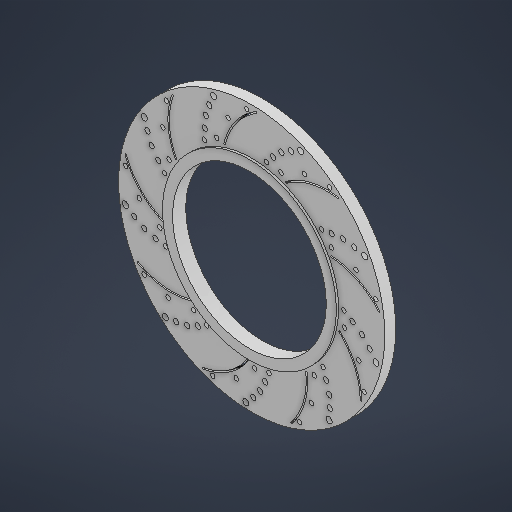
# Autodesk Inventor part: disc2 front face
Saved by Autodesk Inventor 2027 (Build 310192060, 192F)
## iProperties
Created: 2026-07-10
Part Number: disc2 front face
Material: Generic
Document SubType Name: Modeling
Designer: ElieH
Density: 1 g/cm^3
Appearance: Default
Author: ElieH
Autodesk Inventor part; units mm, degrees
ref_plane "YZ Plane" through (0, 0, 0) normal (1, 0, 0) x (0, 1, 0)
ref_plane "XZ Plane" through (0, 0, 0) normal (0, 1, 0) x (-1, 0, 0)
ref_plane "XY Plane" through (0, 0, 0) normal (0, 0, 1) x (1, 0, 0)
sketch "Sketch1" plane through (0, 0, 0) normal (0, 0, 1) x (1, 0, 0)
  arc A0 (-102.94, 86.9125) -> (-99.2877, 29.5739) centre (-33.093, 62.5759) ccw
  arc A1 (-99.5994, 28.6316) -> (-99.2877, 29.5739) centre (-99.9181, 29.2597) ccw
  line L0 (-99.5994, 28.6316) -> (-99.7654, 28.5473)
  arc A2 (-100.7145, 28.8611) -> (-99.7654, 28.5473) centre (-100.0841, 29.1754) ccw
  arc A3 (-104.4457, 87.4385) -> (-100.7145, 28.8611) centre (-33.093, 62.5759) ccw
  arc A4 (-103.5441, 87.8703) -> (-104.4457, 87.4385) centre (-103.7805, 87.2068) ccw
  line L1 (-103.5441, 87.8703) -> (-103.3687, 87.8077)
  arc A5 (-102.94, 86.9125) -> (-103.3687, 87.8077) centre (-103.6051, 87.1443) ccw
  arc A6 (-140.9056, -88.565) -> (-83.804, -94.925) centre (-104.8099, -24.0052) ccw
  arc A7 (-82.93, -95.3955) -> (-83.804, -94.925) centre (-83.6039, -95.6003) ccw
  line L2 (-82.93, -95.3955) -> (-82.8759, -95.5737)
  arc A8 (-83.3497, -96.4538) -> (-82.8759, -95.5737) centre (-83.5498, -95.7785) ccw
  arc A9 (-141.6851, -89.9565) -> (-83.3497, -96.4538) centre (-104.8099, -24.0052) ccw
  arc A10 (-141.9537, -88.9936) -> (-141.6851, -89.9565) centre (-141.3414, -89.3417) ccw
  line L3 (-141.9537, -88.9936) -> (-141.8617, -88.8317)
  arc A11 (-140.9056, -88.565) -> (-141.8617, -88.8317) centre (-141.2494, -89.1798) ccw
  arc A12 (25.3133, -156.4252) -> (41.4923, -101.2954) centre (-31.9977, -109.6672) ccw
  arc A13 (42.1074, -100.5165) -> (41.4923, -101.2954) centre (42.1921, -101.2157) ccw
  line L4 (42.1074, -100.5165) -> (42.2923, -100.4941)
  arc A14 (43.0768, -101.1136) -> (42.2923, -100.4941) centre (42.377, -101.1933) ccw
  arc A15 (26.5483, -157.4345) -> (43.0768, -101.1136) centre (-31.9977, -109.6672) ccw
  arc A16 (25.5534, -157.5318) -> (26.5483, -157.4345) centre (26.0025, -156.9892) ccw
  line L5 (25.5534, -157.5318) -> (25.41, -157.4131)
  arc A17 (25.3133, -156.4252) -> (25.41, -157.4131) centre (25.8591, -156.8705) ccw
  arc A18 (121.0062, -4.5153) -> (69.5234, 20.9911) centre (65.0066, -52.8362) ccw
  arc A19 (68.8631, 21.7321) -> (69.5234, 20.9911) centre (69.5664, 21.6941) ccw
  line L6 (68.8631, 21.7321) -> (68.8732, 21.9181)
  arc A20 (69.6195, 22.5831) -> (68.8732, 21.9181) centre (69.5765, 21.88) ccw
  arc A21 (122.2146, -3.4744) -> (69.6195, 22.5831) centre (65.0066, -52.8362) ccw
  arc A22 (122.1377, -4.471) -> (122.2146, -3.4744) centre (121.6813, -3.9345) ccw
  line L7 (122.1377, -4.471) -> (121.9958, -4.5917)
  arc A23 (121.0062, -4.5153) -> (121.9958, -4.5917) centre (121.5395, -4.0551) ccw
  arc A24 (76.4643, 79.995) -> (20.631, 66.4415) centre (64.6262, 6.9832) ccw
  arc A25 (19.6489, 66.5848) -> (20.631, 66.4415) centre (20.2121, 67.0077) ccw
  line L8 (19.6489, 66.5848) -> (19.537, 66.7337)
  arc A26 (19.6813, 67.7228) -> (19.537, 66.7337) centre (20.1003, 67.1566) ccw
  arc A27 (76.7209, 81.5691) -> (19.6813, 67.7228) centre (64.6262, 6.9832) ccw
  arc A28 (77.3026, 80.7562) -> (76.7209, 81.5691) centre (76.6081, 80.8739) ccw
  line L9 (77.3026, 80.7562) -> (77.2715, 80.5726)
  arc A29 (76.4643, 79.995) -> (77.2715, 80.5726) centre (76.577, 80.6903) ccw
  arc A30 (-70.1457, -152.7445) -> (-22.3152, -120.9123) centre (-83.993, -80.0869) ccw
  arc A31 (-21.3432, -120.711) -> (-22.3152, -120.9123) centre (-21.7278, -121.301) ccw
  line L10 (-21.3432, -120.711) -> (-21.1872, -120.8126)
  arc A32 (-20.9845, -121.7915) -> (-21.1872, -120.8126) centre (-21.5718, -121.4027) ccw
  arc A33 (-69.8484, -154.3114) -> (-20.9845, -121.7915) centre (-83.993, -80.0869) ccw
  arc A34 (-70.6731, -153.7465) -> (-69.8484, -154.3114) centre (-69.9803, -153.6195) ccw
  line L11 (-70.6731, -153.7465) -> (-70.7066, -153.5633)
  arc A35 (-70.1457, -152.7445) -> (-70.7066, -153.5633) centre (-70.0138, -153.4364) ccw
  arc A36 (100.8051, -97.8849) -> (77.7622, -45.2534) centre (26.8468, -98.9051) ccw
  arc A37 (77.7327, -44.2613) -> (77.7622, -45.2534) centre (78.247, -44.7425) ccw
  line L12 (77.7327, -44.2613) -> (77.8599, -44.1253)
  arc A38 (78.8591, -44.0956) -> (77.8599, -44.1253) centre (78.3743, -44.6066) ccw
  arc A39 (102.3999, -97.8643) -> (78.8591, -44.0956) centre (26.8468, -98.9051) ccw
  arc A40 (101.7003, -98.5783) -> (102.3999, -97.8643) centre (101.6956, -97.874) ccw
  line L13 (101.7003, -98.5783) -> (101.5141, -98.5796)
  arc A41 (100.8051, -97.8849) -> (101.5141, -98.5796) centre (101.5094, -97.8752) ccw
  arc A42 (-153.8571, 6.0829) -> (-114.2028, -35.4933) centre (-84.708, 32.3368) ccw
  arc A43 (-113.8358, -36.4156) -> (-114.2028, -35.4933) centre (-114.4837, -36.1393) ccw
  line L14 (-113.8358, -36.4156) -> (-113.9088, -36.5868)
  arc A44 (-114.8376, -36.9565) -> (-113.9088, -36.5868) centre (-114.5567, -36.3105) ccw
  arc A45 (-155.3486, 5.5181) -> (-114.8376, -36.9565) centre (-84.708, 32.3368) ccw
  arc A46 (-154.9355, 6.4283) -> (-155.3486, 5.5181) centre (-154.6901, 5.7681) ccw
  line L15 (-154.9355, 6.4283) -> (-154.7609, 6.4932)
  arc A47 (-153.8571, 6.0829) -> (-154.7609, 6.4932) centre (-154.5156, 5.8329) ccw
  line L16 (-11.8261, 117.2246) -> (-11.7319, 117.064)
  arc A48 (-11.979, 116.1027) -> (-11.7319, 117.064) centre (-12.3395, 116.7077) ccw
  arc A49 (-11.979, 116.1027) -> (-46.0377, 69.8312) centre (25.8836, 52.563) ccw
  arc A50 (-46.8822, 69.3096) -> (-46.0377, 69.8312) centre (-46.7226, 69.9956) ccw
  line L17 (-46.8822, 69.3096) -> (-47.0635, 69.3518)
  arc A51 (-47.5888, 70.2022) -> (-47.0635, 69.3518) centre (-46.904, 70.0378) ccw
  arc A52 (-12.7942, 117.4735) -> (-47.5888, 70.2022) centre (25.8836, 52.563) ccw
  arc A53 (-11.8261, 117.2246) -> (-12.7942, 117.4735) centre (-12.4337, 116.8684) ccw
  circle A54 centre (-17.3598, -23.4491) radius 145.0086
  circle A55 centre (-110.411, 79.1795) radius 2.3772
  circle A56 centre (-154.6095, -4.6432) radius 2.3772
  circle A57 centre (-134.3478, 51.3551) radius 3.2576
  circle A58 centre (-126.4107, 28.7031) radius 2.8174
  circle A59 centre (-112.2284, 9.6418) radius 2.3772
  circle A60 centre (-68.763, 62.8804) radius 2.3772
  circle A61 centre (-67.3749, 86.5984) radius 2.8174
  circle A62 centre (-58.8946, 109.0527) radius 3.2576
  circle A63 centre (-114.1692, 51.9353) radius 2.3772
  circle A64 centre (-130.9248, 40.2025) radius 2.8174
  circle A65 centre (-107.4421, 24.8494) radius 2.3772
  circle A66 centre (-119.1234, 18.3159) radius 2.8174
  circle A67 centre (-43.064, 96.5266) radius 2.3772
  circle A68 centre (-111.3038, -59.0803) radius 2.3772
  circle A69 centre (-155.061, -41.3442) radius 3.2576
  circle A70 centre (-134.4205, -53.5948) radius 2.8174
  circle A71 centre (-134.5874, -97.2653) radius 2.3772
  circle A72 centre (-111.3423, -125.6701) radius 3.2576
  circle A73 centre (-87.6562, -121.7871) radius 2.8174
  circle A74 centre (-66.4218, -111.1302) radius 2.3772
  circle A75 centre (-59.7132, -155.348) radius 2.3772
  circle A76 centre (-108.4097, -105.6974) radius 2.3772
  circle A77 centre (-99.7647, -124.2358) radius 2.8174
  circle A78 centre (-80.5672, -103.7759) radius 2.3772
  circle A79 centre (-76.1613, -116.4142) radius 2.8174
  circle A80 centre (-139.9763, -27.9292) radius 2.3772
  circle A81 centre (-145.2701, -47.6873) radius 2.8174
  circle A82 centre (-23.6482, -162.1657) radius 3.2576
  circle A83 centre (34.9786, -151.7138) radius 2.3772
  circle A84 centre (-7.9995, -143.9661) radius 2.8174
  circle A85 centre (1.4169, -122.1531) radius 2.3772
  circle A86 centre (66.9884, -133.7543) radius 3.2576
  circle A87 centre (67.2774, -109.7537) radius 2.8174
  circle A88 centre (60.4697, -86.9913) radius 2.3772
  circle A89 centre (47.8283, -127.398) radius 2.3772
  circle A90 centre (67.5862, -122.1035) radius 2.8174
  circle A91 centre (63.9822, -97.5005) radius 2.8174
  circle A92 centre (-34.2399, -144.9807) radius 2.3772
  circle A93 centre (-15.7012, -153.625) radius 2.8174
  circle A94 centre (-14.1464, -125.6119) radius 2.3772
  circle A95 centre (-2.6476, -132.4614) radius 2.8174
  circle A96 centre (67.5514, 86.0097) radius 2.3772
  circle A97 centre (35.9932, 104.7512) radius 3.2576
  circle A98 centre (40.0685, 84.9799) radius 2.3772
  circle A99 centre (25.6044, 99.4436) radius 2.8174
  circle A100 centre (15.0636, 93.0012) radius 2.8174
  circle A101 centre (6.0996, 84.0208) radius 2.8174
  circle A102 centre (-1.2454, 75.7244) radius 2.3772
  circle A103 centre (-22.6728, 114.9811) radius 2.3772
  circle A104 centre (105.1807, -88.063) radius 2.3772
  circle A105 centre (118.1575, -53.7298) radius 3.2576
  circle A106 centre (99.3942, -61.1765) radius 2.3772
  circle A107 centre (111.1265, -44.4205) radius 2.8174
  circle A108 centre (102.9516, -35.1585) radius 2.8174
  circle A109 centre (83.8089, -38.0249) radius 2.3772
  circle A110 centre (118.0447, 5.8213) radius 2.3772
  circle A111 centre (83.1052, -22.0974) radius 2.3772
  circle A112 centre (96.3297, 22.6981) radius 2.3772
  circle A113 centre (105.9165, 40.4634) radius 3.2576
  circle A114 centre (94.5465, 43.0753) radius 2.8174
  circle A115 centre (82.3308, 44.9157) radius 2.8174
  circle A116 centre (69.5091, 30.4152) radius 2.3772
  circle A117 centre (92.5511, -27.8901) radius 2.8174
  circle A118 centre (-68.4692, 73.9571) radius 2.8174
  circle A119 centre (-63.4412, 98.309) radius 2.8174
  circle A120 centre (-122.1612, -56.8676) radius 2.8174
  circle A121 centre (-117.4125, -44.354) radius 2.3772
  circle A122 centre (50.7708, -99.6448) radius 2.3772
  circle A123 centre (69.6915, 43.7983) radius 2.8174
  circle A124 centre (58.732, 42.1641) radius 2.3772
  circle A125 centre (14.5623, 73.6516) radius 2.3772
  circle A126 centre (-55.3212, 71.4535) radius 2.3772
  circle A127 centre (-17.3598, -23.4491) radius 94.6473
  circle A128 centre (-17.3598, -23.4491) radius 83.6422
  point P0 (0, 0)
  point P1 (-69.8484, -154.3114)
  point P2 (-70.7066, -153.5633)
  point P3 (-83.804, -94.925)
  point P4 (-82.8759, -95.5737)
  point P5 (-99.5994, 28.6316)
  point P6 (-154.7609, 6.4932)
  point P7 (-153.8571, 6.0829)
  point P8 (-12.7942, 117.4735)
  point P9 (-11.979, 116.1027)
  point P10 (43.0768, -101.1136)
  point P11 (26.5483, -157.4345)
  point P12 (25.41, -157.4131)
  point P13 (19.6489, 66.5848)
  point P14 (76.7209, 81.5691)
  point P15 (77.2715, 80.5726)
  point P16 (76.4643, 79.995)
  point P17 (20.631, 66.4415)
  point P18 (77.7327, -44.2613)
  point P19 (102.3999, -97.8643)
  point P20 (77.7622, -45.2534)
  point P21 (68.8631, 21.7321)
  point P22 (69.6195, 22.5831)
  point P23 (122.2146, -3.4744)
  point P24 (121.9958, -4.5917)
  point P25 (121.0062, -4.5153)
  dimension "d2" = 167.2844
  constraints: 129 centre point, 108 point on circle, 36 end point, 1 coincident
  measures "d2" diameter of A128
extrude "Extrusion1" add sketch "Sketch1" along normal blind 11.875 contours A54
extrude "Extrusion2" add sketch "Sketch1" along normal blind 14.375 contours A127
body "Solid1"
